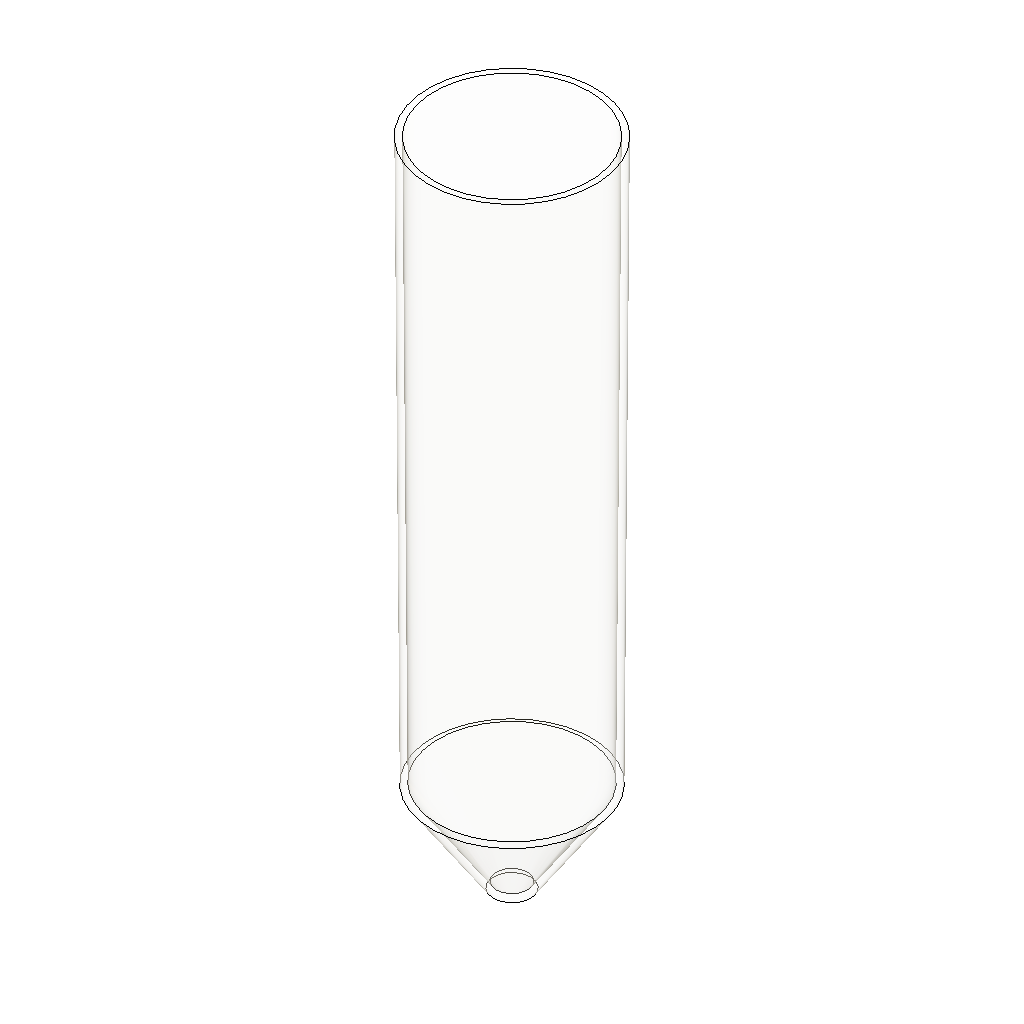
Test Tube (Autodesk Fusion 360 design; units mm, degrees)
part number: 2026-10-19-12-32-30-206
Autodesk Fusion 360 part; units mm, degrees
sketch "Sketch1" plane through (0, 0, 0) normal (1, 0, 0) x (0, 0, -1)
  line L0 (0, 0) -> (-14.575, 0)
  line L1 (0, 0) -> (0, -98) construction
  line L2 (0, -98) -> (-13.9, -98) construction
  line L3 (-13.9, -98) -> (-14.575, 0)
  line L4 (0, -98) -> (0, -113.7346)
  line L5 (0, -113.7346) -> (-3.25, -113.7346)
  line L6 (-3.25, -113.7346) -> (-13.9, -98)
  line L7 (0, -112.7346) -> (-2.7193, -112.7346)
  line L8 (-2.7193, -112.7346) -> (-12.9021, -97.6903)
  line L9 (-12.9021, -97.6903) -> (-13.575, 0)
  dimension "d1" = 14.575
  dimension "d2" = 13.9
  dimension "d3" = 98
  dimension "d4" = 3.25
  dimension "d5" = 19
  dimension "d6" = 1
  constraint coincident L0.start L1.start
  constraint horizontal L0
  constraint perpendicular L0 L1
  constraint perpendicular L1 L2
  constraint perpendicular L2 L4
  constraint perpendicular L4 L5
  constraint coincident L4 L7.start
  constraint coincident L0 L9.end
  measures "d1" distance of L0.start L0.end
  measures "d2" distance of L1.end L2.end
  measures "d3" distance of L0.start L1.end
  measures "d4" distance of L4.end L5.end
  measures "d5" distance of L2.end L5.end
revolve "Revolve1" add sketch "Sketch1" angle 360 about axis through (0, 0, 0) along (0, -1, 0)
equation "d1 = ( 29.15 / 2 ) * 1 mm"
equation "d2 = ( 27.8 / 2 ) * 1 mm"
equation "d4 = ( 6.5 / 2 ) * 1 mm"
